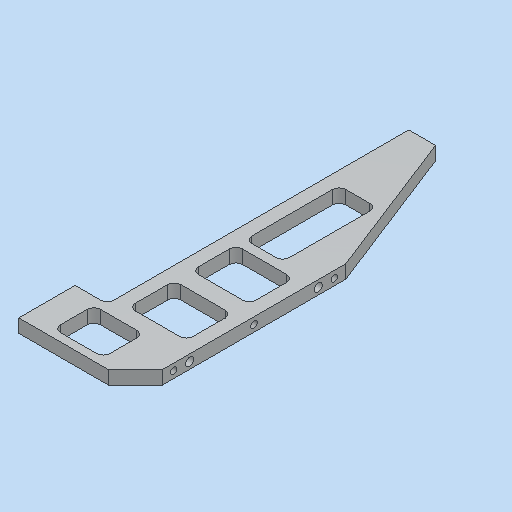
# Autodesk Inventor part: MM0948AN002_G01_113
Saved by Autodesk Inventor 2023.3 (Build 273359000, 359)
## iProperties
RuleStatus: InUse
Created: 2023-04-28
Part Number: MM0948AN002_G01_113
Material: 3.3547 AlMg4,5Mn0,7 - AW 5083
Description: =<RBPARTNOTITLE2>
Document SubType Name: Modeling
Designer: ric7an
Mass: 242.399 g
Surface Area: 337.327 cm^2
Volume: 91.1276 cm^3
Density: 2.66 g/cm^3
Appearance: Aluminium AnP
AnP_Kategorie: 1
AnP_Material: =<Material>
MaxAbmaße: 10 x 267 x 87 (FM)
AnP_TemplVers: 20200821
RBDOCUMENTTYPE: DRF
RBDOCUMENTVERSION: 00
RBDRAWINGMAINSCALE: 1:1
RBDRAWINGMISSINGSPEC: --
RBDRAWINGVOLUME: --
RBDSV1: 0850
RBGBEDGESIN1: +0,5
RBGBEDGESIN2: +0,2
RBGBEDGESOUT1: -0,3
RBGBEDGESOUT2: -0,1
RBMATERIAL: =<Material>
RBMATMEETS: --
RBMATNO: =<Part Number>
RBPARTMADEOF: 10 x 267 x 87 (FM)
RBPARTNO: SIEHE MNR
RBPARTNOTITLE1: manufactured part
RBPARTNOTITLE2: Anfertigungsteil
RBPARTSAFETYINDICATOR: --
RBSURFACE: anodised colourless
RBSURFACE2: eloxiert farblos
RBZEDGESNORM: ISO13715:2002-06
RBZGENDIMCLASS: m
RBZGENDIMNORM: ISO 2768-1:1989-11
RBZGENGEOCLASS: H
RBZGENGEONORM: ISO 2768-2:1989-11
RBZSURFACENORM: ISO13D2:2002-02
RBZTOLERANCENORM: ISO 14405-1:2010-12
Author: ric7an
Keywords: =<RBPARTMADEOF>
Comments: =<RBSURFACE2>
Revision Number: 01
Autodesk Inventor part; units mm, degrees
ref_plane "YZ Plane" through (0, 0, 0) normal (1, 0, 0) x (0, 1, 0)
ref_plane "XZ Plane" through (0, 0, 0) normal (0, 1, 0) x (-1, 0, 0)
ref_plane "XY Plane" through (0, 0, 0) normal (0, 0, 1) x (1, 0, 0)
sketch "Skizze1" plane through (0, 0, 0) normal (0, 0, 1) x (1, 0, 0)
  line L0 (0, 0) -> (63, 0)
  line L1 (63, 0) -> (63, 267)
  line L2 (63, 267) -> (0, 267)
  line L3 (0, 267) -> (0, 0)
  dimension "d0" = 267
  dimension "d1" = 63
  constraints: 8 end point, 2 parallel, 1 horizontal, 1 perpendicular
  measures "d0" distance of L0.end L1.end
  measures "d1" distance of L1.end L2.end
extrude "Extrusion1" add sketch "Skizze1" along normal mid plane 10
sketch "Skizze2" plane through (0, 0, -5) normal (0, 0, -1) x (-1, 0, 0)
  line L0 (-63, 267) -> (-63, 0) projected
  line L1 (-63, 0) -> (0, 0) projected
  line L2 (0, 0) -> (0, 267) projected
  line L3 (0, 267) -> (-63, 267) projected
  line L4 (-63, 157) -> (-20, 267)
  dimension "d4" = 110
  dimension "d5" = 20
  constraints: 2 end point, 2 point on line
  measures "d4" distance from line of L3 L4.start
  measures "d5" distance from line of L2 L4.end
extrude "Extrusion2" cut sketch "Skizze2" against normal through all contours L3 L4 L0
sketch "Skizze3" plane through (63, 0, 5) normal (1, 0, 0) x (0, 0, -1)
  line L0 (5, -53.4) -> (5, 320.4) projected
  line L1 (0, 0) -> (10, 0) projected
  point P0 (5, 0)
  point P1 (5, 28.5)
  point P2 (5, 88.5)
  point P3 (5, 148.5)
  dimension "d8" = 120
  dimension "d9" = 60
  dimension "d10" = 28.5
  constraints: 3 point on line
  measures "d8" distance of point (5, 148.5) point (5, 28.5)
  measures "d9" distance of point (5, 28.5) point (5, 88.5)
  measures "d10" distance from line of L1 point (5, 28.5)
hole "Bohrung1" at (63, 28.5, 0) at (63, 88.5, 0) at (63, 148.5, 0) direction (-1, 0, 0) diameter 4.917 depth 17.1 tip angle 118 thread size "M6x1" designation "M6" class "6H" standard "ISO Metric profile"
sketch "Skizze4" plane through (63, 0, 5) normal (1, 0, 0) x (0, 0, -1)
  circle A0 centre (5, 148.5) radius 2.4585 projected
  circle A1 centre (5, 28.5) radius 2.4585 projected
  point P0 (5, 0)
  point P1 (5, 136.5)
  point P2 (5, 40.5)
  dimension "d18" = 12
  dimension "d19" = 12
  constraints: 2 vertical alignment
  measures "d18" distance of point (5, 136.5) A0.centre
  measures "d19" distance of A1.centre point (5, 40.5)
hole "Bohrung2" at (63, 136.5, 0) at (63, 40.5, 0) direction (-1, 0, 0) diameter 6 depth 15 tip angle 118
chamfer "Fase1" distance 20 angle 45 1 edges at (63, 0, 0)
sketch "Skizze7" plane through (0, 0, 5) normal (-1, 0, 0) x (0, 0, 1)
  line L0 (-5, 320.4) -> (-5, -53.4) projected
  line L1 (-10, 0) -> (0, 0) projected
  point P0 (-5, 0)
  point P1 (-5, 261)
  point P2 (-5, 221)
  dimension "d47" = 40
  dimension "d48" = 221
  constraints: 2 point on line
  measures "d47" distance of point (-5, 221) point (-5, 261)
  measures "d48" distance from line of L1 point (-5, 221)
hole "Bohrung5" at (0, 261, 0) at (0, 221, 0) direction (1, 0, 0) diameter 4.134 depth 14.2 tip angle 118 thread size "M5x0.8" designation "M5" class "6H" standard "ISO Metric profile"
sketch "Skizze10" plane through (0, 0, -5) normal (0, 0, -1) x (-1, 0, 0)
  line L0 (-43, 0) -> (0, 0) projected
  line L1 (0, 0) -> (0, 267) projected
  line L2 (0, 0) -> (24, 0)
  line L3 (24, 0) -> (24, 42)
  line L4 (24, 42) -> (0, 42)
  line L5 (0, 42) -> (0, 0)
  dimension "d72" = 24
  dimension "d73" = 42
  constraints: 8 end point, 2 parallel, 1 horizontal, 1 perpendicular
  measures "d72" distance of L3.end L4.end
  measures "d73" distance of L2.end L3.end
extrude "Extrusion5" add sketch "Skizze10" against normal up to surface (10 mm away)
sketch "Skizze6" plane through (-24, 0, 5) normal (-1, 0, 0) x (0, 0, 1)
  line L0 (-5, 320.4) -> (-5, -53.4) projected
  line L1 (-10, 0) -> (0, 0) projected
  point P0 (-5, 22)
  dimension "d76" = 22
  constraints: 1 point on line
  measures "d76" distance from line of L1 point (-5, 22)
hole "Bohrung4" at (-24, 22, 0) direction (1, 0, 0) diameter 5 depth 12 tip angle 118
sketch "Skizze5" plane through (-24, 0, 5) normal (-1, 0, 0) x (0, 0, 1)
  line L0 (-5, 320.4) -> (-5, -53.4) projected
  line L1 (-10, 0) -> (0, 0) projected
  point P0 (-5, 35)
  point P1 (-5, 10)
  dimension "d28" = 25
  dimension "d77" = 10
  constraints: 2 point on line
  measures "d28" distance of point (-5, 35) point (-5, 10)
  measures "d77" distance from line of L1 point (-5, 10)
hole "Bohrung3" at (-24, 35, 0) at (-24, 10, 0) direction (1, 0, 0) diameter 4.134 depth 14.2 tip angle 118 thread size "M5x0.8" designation "M5" class "6H" standard "ISO Metric profile"
sketch "Skizze9" plane through (0, 0, -5) normal (0, 0, -1) x (-1, 0, 0)
  line L0 (-43, 0) -> (-63, 20) projected
  line L1 (-43, 0) -> (24, 0) projected
  line L2 (0, 42) -> (0, 267) projected
  line L3 (0, 267) -> (-20, 267) projected
  line L4 (-20, 267) -> (-63, 157) projected
  line L5 (-63, 157) -> (-63, 20) projected
  line L6 (-53, 128) -> (-10, 128)
  line L7 (-10, 128) -> (-10, 95)
  line L8 (-10, 95) -> (-53, 95)
  line L9 (-53, 95) -> (-53, 128)
  line L10 (-53, 82) -> (-10, 82)
  line L11 (-10, 82) -> (-10, 48)
  line L12 (-10, 48) -> (-53, 48)
  line L13 (-53, 48) -> (-53, 82)
  line L14 (-10, 135) -> (-38, 135)
  line L15 (-38, 135) -> (-38, 205)
  line L16 (-38, 205) -> (-10, 205)
  line L17 (-10, 205) -> (-10, 135)
  line L18 (24, 0) -> (24, 42) projected
  line L19 (24, 42) -> (0, 42) projected
  line L20 (-33, 36) -> (4, 36)
  line L21 (4, 36) -> (4, 6)
  line L22 (4, 6) -> (-33, 6)
  line L23 (-33, 6) -> (-33, 36)
  point P0 (0, 0)
  dimension "d61" = 10
  dimension "d62" = 10
  dimension "d63" = 48
  dimension "d64" = 34
  dimension "d65" = 25
  dimension "d66" = 70
  dimension "d67" = 95
  dimension "d68" = 33
  dimension "d69" = 135
  dimension "d78" = 6
  dimension "d80" = 20
  dimension "d81" = 30
  dimension "d82" = 6
  constraints: 32 end point, 8 parallel, 4 horizontal, 4 perpendicular, 3 point on line
  measures "d61" distance between parallel lines of L2 L11
  measures "d62" distance between parallel lines of L13 L5
  measures "d63" distance between parallel lines of L1 L12
  measures "d64" distance of L10.end L11.end
  measures "d65" distance between parallel lines of L5 L15
  measures "d66" distance of L16.end L14.start
  measures "d67" distance between parallel lines of L1 L8
  measures "d68" distance of L6.end L7.end
  measures "d69" distance between parallel lines of L1 L14
  measures "d78" distance between parallel lines of L1 L22
  measures "d80" distance between parallel lines of L18 L21
  measures "d81" distance between parallel lines of L23 L5
  measures "d82" distance between parallel lines of L20 L19
extrude "Extrusion4" cut sketch "Skizze9" against normal through all contours L6 L7 L8 L9 | L10 L11 L12 L13 | L14 L15 L16 L17 | L20 L21 L22 L23
fillet "Rundung1" radius 5 17 edges at (0, 42, 0) (33, 36, 0) (-4, 36, 0) (-4, 6, 0) (33, 6, 0) (53, 48, 0) (53, 82, 0) (10, 82, 0) (10, 48, 0) (10, 95, 0) (53, 95, 0) (53, 128, 0) (10, 128, 0) (10, 135, 0) (38, 135, 0) (38, 205, 0) (10, 205, 0)
equation "\"d9\" = 0.5 * d8"
